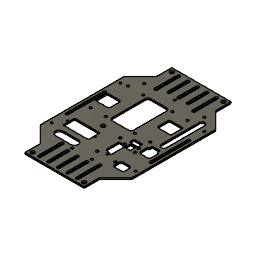
sheet for pi_lidar_optical_flow (Autodesk Fusion 360 design; units mm, degrees)
Autodesk Fusion 360 part; units mm, degrees
sketch "Sketch1" plane through (0, 0, 0) normal (0, 0, 1) x (1, 0, 0)
  line L0 (60, 55) -> (-60, 55)
  line L1 (-60, 55) -> (-60, -55)
  line L2 (-60, -55) -> (60, -55)
  line L3 (60, -55) -> (60, 55)
  line L4 (60, 55) -> (-60, -55) construction
  line L5 (-60, 55) -> (60, -55) construction
  line L6 (-60, 55) -> (-38.7868, 76.2132)
  line L7 (-60, 55) -> (-25, 55) construction
  line L8 (-38.7868, 76.2132) -> (-38.7868, 96.2132)
  line L9 (-38.7868, 96.2132) -> (38.7868, 96.2132)
  line L10 (38.7868, 96.2132) -> (38.7868, 76.2132)
  line L11 (38.7868, 76.2132) -> (60, 55)
  line L12 (70, 0) -> (110, 0)
  line L13 (-38.7868, -76.2132) -> (-38.7868, -96.2132)
  line L14 (-38.7868, -96.2132) -> (38.7868, -96.2132)
  line L15 (38.7868, -96.2132) -> (38.7868, -76.2132)
  line L16 (38.7868, -76.2132) -> (60, -55)
  line L17 (-60, -55) -> (-38.7868, -76.2132)
  dimension "d1" = 120
  dimension "d2" = 110
  dimension "d55" = 45
  dimension "d56" = 30
  dimension "d57" = 20
  dimension "d58" = 45
  constraint horizontal L0
  constraint perpendicular L0 L1
  constraint parallel L0 L2
  constraint parallel L1 L3
  constraint coincident L4 origin
  constraint coincident L5 origin
  constraint horizontal L7
  constraint perpendicular L0 L8
  constraint perpendicular L1 L9
  constraint perpendicular L9 L10
  constraint equal L6 L11
  constraint perpendicular L3 L12
  constraint symmetric L0.start L12 L2.end
  constraint symmetric L0.end L12 L1.end
  constraint symmetric L6.end L12 L13.start
  constraint symmetric L8.end L12 L13.end
  constraint symmetric L9.end L12 L14.end
  constraint symmetric L10.end L12 L15.end
  measures "d1" distance of L1.end L2.end
  measures "d2" distance of L0.end L1.end
  measures "d55" angle of L6 L7
  measures "d56" distance of L0.end L6.end
  measures "d57" distance of L6.end L8.end
  measures "d58" angle of L0 L11
extrude "Extrude1" add sketch "Sketch1" along normal blind 2
sketch "Sketch2" plane through (0, 0, 2) normal (0, 0, 1) x (-1, 0, 0)
  line L0 (-60, 55) -> (-60, -55)
  line L1 (60, -55) -> (60, 55)
  line L2 (45, 25) -> (12, 25)
  line L3 (12, 25) -> (12, 40)
  line L4 (12, 40) -> (45, 40)
  line L5 (45, 40) -> (45, 25)
  line L6 (-4.5, 15) -> (-50, 15)
  line L7 (-50, 15) -> (-50, 50)
  line L8 (-50, 50) -> (-4.5, 50)
  line L9 (-4.5, 50) -> (-4.5, 15)
  line L10 (50, -50) -> (-35, -50)
  line L11 (-35, -50) -> (-35, 6)
  line L12 (-35, 6) -> (50, 6)
  line L13 (50, 6) -> (50, -50)
  line L14 (55, 55) -> (-55, 55)
  line L15 (-55, 55) -> (-55, -55)
  line L16 (-55, -55) -> (55, -55)
  line L17 (55, -55) -> (55, 55)
  line L18 (60, 55) -> (38.7868, 76.2132)
  line L19 (38.7868, 76.2132) -> (38.7868, 96.2132)
  line L20 (38.7868, 96.2132) -> (-38.7868, 96.2132)
  line L21 (-38.7868, 96.2132) -> (-38.7868, 76.2132)
  line L22 (-38.7868, 76.2132) -> (-60, 55)
  line L23 (-60, -55) -> (-38.7868, -76.2132)
  line L24 (-38.7868, -76.2132) -> (-38.7868, -96.2132)
  line L25 (-38.7868, -96.2132) -> (38.7868, -96.2132)
  line L26 (38.7868, -96.2132) -> (38.7868, -76.2132)
  line L27 (38.7868, -76.2132) -> (60, -55)
  dimension "d5" = 33
  dimension "d6" = 15
  dimension "d7" = 45.5
  dimension "d8" = 35
  dimension "d9" = 85
  dimension "d10" = 56
  dimension "d13" = 5
  dimension "d14" = 5
  dimension "d15" = 5
  dimension "d16" = 5
  constraint horizontal L2
  constraint vertical L3
  constraint horizontal L4
  constraint vertical L5
  constraint horizontal L6
  constraint vertical L7
  constraint horizontal L8
  constraint vertical L9
  constraint horizontal L10
  constraint vertical L11
  constraint horizontal L12
  constraint vertical L13
  measures "d5" distance of L2.start L2.end
  measures "d6" distance of L2.start L4.end
  measures "d7" distance of L6.start L6.end
  measures "d8" distance of L6.start L8.end
  measures "d9" distance of L10.start L10.end
  measures "d10" distance of L10.start L12.end
  measures "d13" distance of L8 L14
  measures "d14" distance of L7 L15
  measures "d15" distance of L10 L16
  measures "d16" distance of L13 L17
sketch "px4 flow" plane through (0, 0, 2) normal (0, 0, 1) x (-1, 0, 0)
  line L0 (-4.5, 49) -> (-4.5, 15)
  line L1 (-50, 16) -> (-50, 49)
  line L2 (-5.5, 15) -> (-13, 15)
  line L3 (-13, 50) -> (-5.5, 50)
  line L4 (-4.5, 50) -> (-4.5, 16)
  line L5 (-34, 50) -> (-27, 50)
  line L6 (-27, 50) -> (-27, 16)
  line L7 (-29, 15) -> (-34, 15)
  line L8 (-38, 22) -> (-48, 22)
  line L9 (-50, 22) -> (-50, 43)
  line L10 (-45.6317, 43) -> (-36, 43)
  line L11 (-12.2169, 22.2704) -> (-18.4339, 23.652)
  line L12 (-20, 25.6043) -> (-20, 40.7534)
  line L13 (-18.7831, 41.7296) -> (-12.5661, 40.348)
  line L14 (-11, 38.3957) -> (-11, 23.2466)
  line L15 (-13, 15) -> (-13, 22.4444)
  line L16 (-13, 40.4444) -> (-13, 50)
  line L17 (-34, 45) -> (-34, 50)
  line L18 (-18, 15) -> (-19, 16)
  line L19 (-19, 16) -> (-27, 16)
  line L20 (-28, 16) -> (-29, 15)
  line L21 (-4.5, 15) -> (-18, 15)
  line L22 (-29, 15) -> (-36, 15)
  line L23 (-48, 22) -> (-50, 20)
  line L24 (-38, 22) -> (-36, 20)
  line L25 (-38, 22) -> (-35.1716, 22) construction
  line L26 (-36, 20) -> (-36, 15)
  line L27 (-50, 15) -> (-50, 50)
  arc A0 (-5.5, 15) -> (-4.5, 16) centre (-5.5, 16) ccw
  arc A1 (-4.5, 49) -> (-5.5, 50) centre (-5.5, 49) ccw
  arc A2 (-49, 50) -> (-50, 49) centre (-49, 49) ccw
  line L28 (-34, 45) -> (-36, 43)
  line L29 (-45.6317, 43) -> (-47.6317, 45)
  line L30 (-47.6317, 45) -> (-47.6317, 50)
  arc A3 (-12.2169, 22.2704) -> (-11, 23.2466) centre (-12, 23.2466) ccw
  arc A4 (-18.7831, 41.7296) -> (-20, 40.7534) centre (-19, 40.7534) ccw
  arc A5 (-20, 25.6043) -> (-18.4339, 23.652) centre (-18, 25.6043) ccw
  arc A6 (-11, 38.3957) -> (-12.5661, 40.348) centre (-13, 38.3957) ccw
  line L31 (-27, 16) -> (-28, 16)
  circle A7 centre (-7.1329, 17.151) radius 1.6654
  circle A8 centre (-31.1939, 17.1993) radius 1.6186
  circle A9 centre (-33.3, 24.1) radius 1.5796
  circle A10 centre (-31.1536, 47.5993) radius 1.6164
  circle A11 centre (-7.1536, 47.551) radius 1.638
  line L32 (-4.5, 15) -> (-50, 15)
  circle A12 centre (-17.1004, 43.6134) radius 1.713
  circle A13 centre (-17.2367, 21.5536) radius 1.75
  line L33 (-18, 15) -> (-18, 10.5)
  line L34 (-18.5, 10) -> (-28.5, 10)
  line L35 (-29, 10.5) -> (-29, 15)
  line L36 (-36, 15) -> (-36, 10.5)
  line L37 (-50, 10.5) -> (-50, 16)
  arc A14 (-18.5, 10) -> (-18, 10.5) centre (-18.5, 10.5) ccw
  arc A15 (-29, 10.5) -> (-28.5, 10) centre (-28.5, 10.5) ccw
  arc A16 (-36.5, 10) -> (-36, 10.5) centre (-36.5, 10.5) ccw
  arc A17 (-50, 10.5) -> (-49.5, 10) centre (-49.5, 10.5) ccw
  line L38 (-28, 25) -> (-20.7592, 25)
  line L39 (-20.7592, 25) -> (-20.7592, 17.3949)
  line L40 (-20.7592, 17.3949) -> (-28, 17.3949)
  line L41 (-28, 17.3949) -> (-28, 25)
  line L42 (-47.6317, 50) -> (-47.6317, 52)
  line L43 (-45.6317, 54) -> (-36, 54)
  line L44 (-34, 52) -> (-34, 50)
  line L45 (-48, 9.5) -> (-48, 6)
  line L46 (-48, 6) -> (-38, 6)
  line L47 (-38, 6) -> (-38, 9.5)
  line L48 (-36.5, 10) -> (-37.5, 10)
  line L49 (-48.5, 10) -> (-49.5, 10)
  arc A18 (-37.5, 10) -> (-38, 9.5) centre (-37.5, 9.5) ccw
  arc A19 (-48, 9.5) -> (-48.5, 10) centre (-48.5, 9.5) ccw
  arc A20 (-34, 52) -> (-36, 54) centre (-36, 52) ccw
  arc A21 (-45.6317, 54) -> (-47.6317, 52) centre (-45.6317, 52) ccw
  line L50 (-49, 50) -> (-47.6317, 50)
  line L51 (-34, 50) -> (-4.5, 50)
  point P0 (-34, 54)
  dimension "d17" = 45
  dimension "d18" = 45
  dimension "d19" = 1
  dimension "d20" = 90
  dimension "d21" = 1
  dimension "d22" = 2
  dimension "d23" = 30.4
  dimension "d24" = 24
  dimension "d25" = 30.4
  dimension "d26" = 3.2373
  dimension "d27" = 9.1
  dimension "d28" = 16.7
  dimension "d29" = 0.5
  dimension "d105" = 3.5
  dimension "d106" = 4
  dimension "d107" = 0.5
  dimension "d108" = 2
  constraint horizontal L2
  constraint vertical L15
  constraint horizontal L3
  constraint vertical L4
  constraint coincident L3.start L51
  constraint horizontal L5
  constraint vertical L6
  constraint horizontal L7
  constraint horizontal L8
  constraint vertical L9
  constraint horizontal L10
  constraint coincident L1 L9.end
  constraint parallel L12 L16
  constraint parallel L11 L13
  constraint parallel L14 L15
  constraint coincident L11 L15.end
  constraint coincident L13 L16.start
  constraint collinear L15 L16
  constraint perpendicular L6 L19
  constraint collinear L21 L22
  constraint coincident L1 L23.end
  constraint horizontal L25
  constraint perpendicular L22 L26
  constraint coincident L0.end L4
  constraint coincident L0.end L2
  constraint tangent L4 A0
  constraint tangent L2 A0
  constraint coincident L4.start L0
  constraint coincident L4.start L3
  constraint tangent L0 A1
  constraint tangent L3 A1
  constraint equal A0 A1
  constraint tangent A2 L50
  constraint tangent L1 A2
  constraint equal A0 A2
  constraint perpendicular L30 L50
  constraint tangent L11 A3
  constraint tangent L14 A3
  constraint tangent L12 A4
  constraint tangent L13 A4
  constraint equal A3 A4
  constraint tangent L11 A5
  constraint tangent L12 A5
  constraint tangent L13 A6
  constraint tangent L14 A6
  constraint equal A5 A6
  constraint perpendicular L21 L33
  constraint perpendicular L33 L34
  constraint vertical L35
  constraint perpendicular L32 L36
  constraint perpendicular L26 L48
  constraint tangent L33 A14
  constraint tangent L34 A14
  constraint tangent L34 A15
  constraint tangent L35 A15
  constraint equal A14 A15
  constraint tangent L36 A16
  constraint tangent A16 L48
  constraint equal A14 A16
  constraint tangent A17 L49
  constraint tangent L37 A17
  constraint equal A14 A17
  constraint horizontal L38
  constraint vertical L39
  constraint horizontal L40
  constraint vertical L41
  constraint parallel L42 L44
  constraint vertical L45
  constraint horizontal L46
  constraint vertical L47
  constraint collinear L48 L49
  constraint tangent L47 A18
  constraint tangent L48 A18
  constraint tangent L45 A19
  constraint tangent L49 A19
  constraint equal A18 A19
  constraint coincident P0 L43
  constraint coincident P0 L44
  constraint tangent L43 A20
  constraint tangent L44 A20
  constraint tangent L42 A21
  constraint tangent L43 A21
  constraint equal A20 A21
  constraint collinear L50 L51
  measures "d17" angle of L24 L25
  measures "d18" angle of L23 L27
  measures "d19" radius of A0
  measures "d20" angle of L28 L29
  measures "d21" radius of A3
  measures "d22" radius of A5
  measures "d23" vertical distance of A7.centre A11.centre
  measures "d24" horizontal distance of A10.centre A11.centre
  measures "d25" vertical distance of A8.centre A10.centre
  measures "d26" diameter of A8
  measures "d27" distance of A9.centre L32
  measures "d28" distance of L27 A9.centre
  measures "d29" radius of A14
  measures "d105" diameter of A13
  measures "d106" distance of L5.start P0
  measures "d107" radius of A18
  measures "d108" radius of A20
sketch "Raspberry Pi" plane through (0, 0, 2) normal (0, 0, 1) x (-1, 0, 0)
  line L0 (-35, 6) -> (50, 6)
  line L1 (50, 6) -> (50, -50)
  line L2 (-35, -50) -> (-35, 6)
  line L3 (50, -50) -> (-35, -50)
  line L4 (50, 6) -> (50, -50)
  line L5 (50, -25) -> (36, -25)
  line L6 (34, -23) -> (34, -11)
  line L7 (36, -9) -> (50, -9)
  line L8 (50, -9) -> (50, -25)
  line L9 (-35, 6) -> (50, 6)
  line L10 (-35, -35) -> (-21, -35)
  line L11 (-19, -33) -> (-19, -21)
  line L12 (-21, -19) -> (-35, -19)
  line L13 (-35, -19) -> (-35, -35)
  line L14 (-35, -50) -> (-35, 6)
  line L15 (17.5, -47) -> (-3.5, -47)
  line L16 (-7, -43.5) -> (-7, -0.5)
  line L17 (-3.5, 3) -> (17.5, 3)
  line L18 (21, -0.5) -> (21, -43.5)
  arc A0 (17.5, -47) -> (21, -43.5) centre (17.5, -43.5) ccw
  arc A1 (-7, -43.5) -> (-3.5, -47) centre (-3.5, -43.5) ccw
  arc A2 (21, -0.5) -> (17.5, 3) centre (17.5, -0.5) ccw
  arc A3 (-3.5, 3) -> (-7, -0.5) centre (-3.5, -0.5) ccw
  arc A4 (34, -23) -> (36, -25) centre (36, -23) ccw
  arc A5 (36, -9) -> (34, -11) centre (36, -11) ccw
  arc A6 (-21, -35) -> (-19, -33) centre (-21, -33) ccw
  arc A7 (-19, -21) -> (-21, -19) centre (-21, -21) ccw
  line L19 (50, -25) -> (52, -25)
  line L20 (52, -25) -> (52, -9)
  line L21 (52, -9) -> (50, -9)
  line L22 (50, -9) -> (50, -25)
  line L23 (-35, -35) -> (-37, -35)
  line L24 (-37, -35) -> (-37, -19)
  line L25 (-37, -19) -> (-35, -19)
  line L26 (-35, -19) -> (-35, -35)
  point P0 (46.5, -46.5)
  point P1 (46.5, 2.5)
  point P2 (-11.5, -46.5)
  point P3 (-11.5, 2.5)
  point P4 (-31.5, -46.5)
  point P5 (-31.5, 2.5)
  point P6 (26.5, -46.5)
  point P7 (26.5, 2.5)
  point P8 (34, -25)
  dimension "d30" = 3.5
  dimension "d31" = 3.5
  dimension "d32" = 3.5
  dimension "d33" = 3.5
  dimension "d34" = 3.5
  dimension "d35" = 3.5
  dimension "d36" = 3.5
  dimension "d37" = 3.5
  dimension "d38" = 58
  dimension "d39" = 49
  dimension "d40" = 16
  dimension "d41" = 25
  dimension "d42" = 15
  dimension "d43" = 15
  dimension "d44" = 25
  dimension "d45" = 16
  dimension "d46" = 3.5
  dimension "d47" = 2
  constraint horizontal L5
  constraint vertical L6
  constraint horizontal L7
  constraint vertical L8
  constraint coincident L1 L5.start
  constraint horizontal L10
  constraint vertical L11
  constraint horizontal L12
  constraint vertical L13
  constraint coincident L2 L10.start
  constraint horizontal L15
  constraint vertical L16
  constraint horizontal L17
  constraint vertical L18
  constraint tangent L15 A0
  constraint tangent L18 A0
  constraint tangent L15 A1
  constraint tangent L16 A1
  constraint equal A0 A1
  constraint tangent L18 A2
  constraint tangent L17 A2
  constraint equal A0 A2
  constraint tangent L16 A3
  constraint tangent L17 A3
  constraint equal A0 A3
  constraint coincident P8 L5
  constraint coincident P8 L6
  constraint tangent L5 A4
  constraint tangent L6 A4
  constraint tangent L6 A5
  constraint tangent L7 A5
  constraint equal A4 A5
  constraint tangent L10 A6
  constraint tangent L11 A6
  constraint equal A4 A6
  constraint tangent L11 A7
  constraint tangent L12 A7
  constraint equal A4 A7
  constraint horizontal L19
  constraint vertical L20
  constraint horizontal L21
  constraint vertical L22
  constraint horizontal L23
  constraint vertical L24
  constraint horizontal L25
  constraint vertical L26
  measures "d30" distance of L1 P0
  measures "d31" distance of L3 P0
  measures "d32" distance of P1 L4
  measures "d33" distance of L0 P1
  measures "d34" distance of L2 P4
  measures "d35" distance of L2 P5
  measures "d36" distance of L3 P4
  measures "d37" distance of L0 P5
  measures "d38" distance of P0 P2
  measures "d39" distance of P2 P3
  measures "d40" distance of L5.start P8
  measures "d41" distance of L3 L5
  measures "d42" distance of L7 L9
  measures "d43" distance of L3 L10
  measures "d44" distance of L9 L12
  measures "d45" distance of L11 L14
  measures "d46" radius of A0
  measures "d47" radius of A4
sketch "tf mini lidar" plane through (0, 0, 2) normal (0, 0, 1) x (-1, 0, 0)
  line L0 (12.5, 40) -> (44.5, 40)
  line L1 (45, 39.5) -> (45, 25.5)
  line L2 (12, 25.5) -> (12, 39.5)
  line L3 (44.5, 25) -> (12.5, 25)
  circle A0 centre (46.5, 32.5) radius 1.175
  circle A1 centre (10.5, 32.5) radius 1.175
  line L4 (12, 25) -> (12, 40)
  arc A2 (44.5, 25) -> (45, 25.5) centre (44.5, 25.5) ccw
  arc A3 (45, 39.5) -> (44.5, 40) centre (44.5, 39.5) ccw
  arc A4 (12.5, 40) -> (12, 39.5) centre (12.5, 39.5) ccw
  arc A5 (12, 25.5) -> (12.5, 25) centre (12.5, 25.5) ccw
  dimension "d48" = 36
  dimension "d49" = 1.5
  dimension "d50" = 2.35
  dimension "d51" = 2.35
  dimension "d52" = 7.5
  dimension "d53" = 7.5
  dimension "d54" = 0.5
  constraint tangent L1 A2
  constraint tangent L3 A2
  constraint tangent L0 A3
  constraint tangent L1 A3
  constraint equal A2 A3
  constraint tangent L0 A4
  constraint tangent L2 A4
  constraint equal A2 A4
  constraint tangent L2 A5
  constraint tangent L3 A5
  constraint equal A2 A5
  measures "d48" horizontal distance of A0.centre A1.centre
  measures "d49" distance of A1.centre L4
  measures "d50" diameter of A1
  measures "d51" diameter of A0
  measures "d52" distance of L3 A0.centre
  measures "d53" distance of L3 A1.centre
  measures "d54" radius of A2
sketch "holes" plane through (0, 0, 2) normal (0, 0, 1) x (-1, 0, 0)
  line L0 (60, -55) -> (60, 55)
  line L1 (60, 55) -> (38.7868, 76.2132)
  line L2 (38.7868, 76.2132) -> (38.7868, 96.2132)
  line L3 (38.7868, 96.2132) -> (-38.7868, 96.2132)
  line L4 (-38.7868, 96.2132) -> (-38.7868, 76.2132)
  line L5 (-38.7868, 76.2132) -> (-60, 55)
  line L6 (-60, 55) -> (-60, -55)
  line L7 (-60, -55) -> (-38.7868, -76.2132)
  line L8 (-38.7868, -76.2132) -> (-38.7868, -96.2132)
  line L9 (-38.7868, -96.2132) -> (38.7868, -96.2132)
  line L10 (38.7868, -96.2132) -> (38.7868, -76.2132)
  line L11 (38.7868, -76.2132) -> (60, -55)
  line L12 (56.5, -25) -> (56.5, 25)
  arc A0 (56.5, 25) -> (53.5, 25) centre (55, 25) ccw
  line L13 (53.5, 25) -> (53.5, -25)
  arc A1 (53.5, -25) -> (56.5, -25) centre (55, -25) ccw
  line L14 (55, -25) -> (55, 25) construction
  line L15 (-53.5, -25) -> (-53.5, 25)
  arc A2 (-53.5, 25) -> (-56.5, 25) centre (-55, 25) ccw
  line L16 (-56.5, 25) -> (-56.5, -25)
  arc A3 (-56.5, -25) -> (-53.5, -25) centre (-55, -25) ccw
  line L17 (-55, -25) -> (-55, 25) construction
  line L18 (38, 57) -> (18, 57)
  arc A4 (18, 57) -> (18, 47) centre (18, 52) ccw
  line L19 (18, 47) -> (38, 47)
  arc A5 (38, 47) -> (38, 57) centre (38, 52) ccw
  line L20 (38, 52) -> (18, 52) construction
  line L21 (-41.5, -52) -> (-41.5, -2)
  arc A6 (-41.5, -2) -> (-48.5, -2) centre (-45, -2) ccw
  line L22 (-48.5, -2) -> (-48.5, -52)
  arc A7 (-48.5, -52) -> (-41.5, -52) centre (-45, -52) ccw
  line L23 (-45, -52) -> (-45, -2) construction
  point P0 (55, -45)
  point P1 (-55, -45)
  point P2 (55, 45)
  point P3 (-55, 45)
  point P4 (12.9288, 60.3583)
  point P5 (-12.9288, 60.2132)
  point P6 (38.7872, -60)
  point P7 (-38.7868, -61.0687)
  point P8 (0.0002, -61.0687)
  point P9 (33.7868, 91.2132)
  point P10 (-33.7868, 91.2132)
  point P11 (33.7868, -91.2132)
  point P12 (-33.7868, -91.2132)
  point P13 (17.6878, 14.8368)
  dimension "d60" = 3
  dimension "d61" = 3
  dimension "d62" = 110
  dimension "d63" = 5
  dimension "d64" = 5
  dimension "d65" = 50
  dimension "d66" = 50
  dimension "d67" = 30
  dimension "d68" = 5
  dimension "d69" = 5
  dimension "d70" = 5
  dimension "d71" = 5
  dimension "d72" = 10
  dimension "d73" = 10
  dimension "d74" = 10
  dimension "d75" = 10
  dimension "d76" = 25.858
  dimension "d77" = 25.858
  dimension "d78" = 25.858
  dimension "d79" = 16
  dimension "d80" = 77.574
  dimension "d81" = 38.787
  dimension "d82" = 38.787
  dimension "d83" = 50
  dimension "d84" = 7
  dimension "d85" = 5
  dimension "d86" = 5
  dimension "d87" = 5
  dimension "d88" = 5
  dimension "d89" = 5
  dimension "d90" = 5
  dimension "d91" = 5
  dimension "d92" = 5
  dimension "d109" = 3
  constraint tangent L12 A0
  constraint tangent A0 L13
  constraint parallel L12 L13
  constraint tangent L13 A1
  constraint tangent L12 A1
  constraint parallel L0 L14
  constraint tangent L15 A2
  constraint tangent A2 L16
  constraint parallel L15 L16
  constraint tangent L16 A3
  constraint tangent L15 A3
  constraint parallel L6 L17
  constraint tangent L18 A4
  constraint tangent A4 L19
  constraint parallel L18 L19
  constraint tangent L19 A5
  constraint tangent L18 A5
  constraint perpendicular L0 L20
  constraint tangent L21 A6
  constraint tangent A6 L22
  constraint parallel L21 L22
  constraint tangent L22 A7
  constraint tangent L21 A7
  constraint vertical L23
  measures "d60" diameter of A0
  measures "d61" diameter of A2
  measures "d62" distance of A1.centre A3.centre
  measures "d63" distance of L0 A1.centre
  measures "d64" distance of L6 A3.centre
  measures "d65" distance of A3.centre A2.centre
  measures "d66" distance of A1.centre A0.centre
  measures "d67" vertical distance of L6.end A3.centre
  measures "d68" distance of L0 P0
  measures "d69" distance of L0 P2
  measures "d70" distance of L6 P3
  measures "d71" distance of L6 P1
  measures "d72" vertical distance of L6.end P1
  measures "d73" vertical distance of L0.start P0
  measures "d74" vertical distance of L0.end P2
  measures "d75" vertical distance of L5.end P3
  measures "d76" distance of L2 P4
  measures "d77" distance of L4 P5
  measures "d78" distance of P4 P5
  measures "d79" vertical distance of L4.end P5
  measures "d80" distance of L8 P6
  measures "d81" horizontal distance of P6 P8
  measures "d82" distance of P7 P8
  measures "d83" distance of A7.centre A6.centre
  measures "d84" diameter of A6
  measures "d85" distance of L10 P11
  measures "d86" distance of L9 P11
  measures "d87" vertical distance of L8.end P12
  measures "d88" horizontal distance of L8.end P12
  measures "d89" distance of L2 P9
  measures "d90" distance of L4 P10
  measures "d91" vertical distance of L2.end P9
  measures "d92" vertical distance of L3.end P10
  measures "d109" vertical distance of L6.end A7.centre
hole "Hole1" at (-38.7872, 60, 2) at (-0.0002, 61.0687, 2) at (38.7868, 61.0687, 2) at (-55, 45, 2) at (-55, -45, 2) at (-12.9288, -60.3583, 2) at (12.9288, -60.2132, 2) at (55, -45, 2) at (55, 45, 2) at (-46.5, 46.5, 2) at (-46.5, -2.5, 2) at (-26.5, 46.5, 2) at (-26.5, -2.5, 2) at (11.5, 46.5, 2) at (31.5, 46.5, 2) at (11.5, -2.5, 2) at (31.5, -2.5, 2) direction (0, 0, -1) diameter 3 depth 50 tip angle 180
extrude "Extrude2" cut sketch "holes" sketch "tf mini lidar" against normal blind 20 contours L12 A0 L13 A1 | L15 A2 L16 A3 | L18 A4 L19 A5 | L21 A6 L22 A7 of sketch 2
hole "Hole2" at (-33.7868, 91.2132, 2) at (33.7868, 91.2132, 2) at (-33.7868, -91.2132, 2) at (33.7868, -91.2132, 2) at (-17.6878, -14.8368, 2) direction (0, 0, -1) diameter 5 depth 50 tip angle 180
extrude "Extrude3" cut sketch "Raspberry Pi" against normal blind 15 contours L2 L10 L11 L12 L13 L14 A6 A7 L26 | L2 L13 L14 L23 L24 L25 L26 | L1 L4 L8 L19 L20 L21 L22 | L1 L4 L5 L6 L7 L8 A4 A5 L22 | L15 L16 L17 L18 A0 A1 A2 A3
extrude "Extrude4" cut sketch "px4 flow" against normal blind 7 contours L11 L12 L13 L14 A3 A4 A5 A6 | L18 L19 L20 L31 L32 | L32 L33 L34 L35 A14 A15 | L10 L17 L28 L29 L30 L42 L43 L44 A20 A21 | L6 L38 L39 L40 | L6 L38 L40 L41 | L1 L8 L23 L24 L26 L27 L32 L37 | L32 L36 L37 A16 A17 L45 L46 L47 L48 L49 A18 A19 | A7 | A8 | A9 | A10 | A11 | A12 | A13
sketch "Sketch7" plane through (0, 0, 2) normal (0, 0, 1) x (-1, 0, 0)
  circle A0 centre (-31.1536, 47.5993) radius 1.6164
  circle A1 centre (-17.2367, 21.5536) radius 1.75
  line L0 (-27, 16) -> (-19, 16)
  line L1 (-19, 16) -> (-18, 15)
  line L2 (-18, 15) -> (-18, 10.5)
  arc A2 (-18.5, 10) -> (-18, 10.5) centre (-18.5, 10.5) ccw
  line L3 (-18.5, 10) -> (-28.5, 10)
  arc A3 (-29, 10.5) -> (-28.5, 10) centre (-28.5, 10.5) ccw
  line L4 (-29, 10.5) -> (-29, 15)
  line L5 (-29, 15) -> (-28, 16)
  line L6 (-28, 16) -> (-27, 16)
  circle A4 centre (-17.1004, 43.6134) radius 1.713
  circle A5 centre (-33.3, 24.1) radius 1.5796
  line L7 (-45.6317, 43) -> (-47.6317, 45)
  line L8 (-47.6317, 45) -> (-47.6317, 52)
  arc A6 (-45.6317, 54) -> (-47.6317, 52) centre (-45.6317, 52) ccw
  line L9 (-45.6317, 54) -> (-36, 54)
  arc A7 (-34, 52) -> (-36, 54) centre (-36, 52) ccw
  line L10 (-34, 52) -> (-34, 50)
  line L11 (-34, 50) -> (-34, 45)
  line L12 (-34, 45) -> (-36, 43)
  line L13 (-36, 43) -> (-45.6317, 43)
  line L14 (-50, 20) -> (-48, 22)
  line L15 (-48, 22) -> (-38, 22)
  line L16 (-38, 22) -> (-36, 20)
  line L17 (-36, 20) -> (-36, 10.5)
  arc A8 (-36.5, 10) -> (-36, 10.5) centre (-36.5, 10.5) ccw
  line L18 (-36.5, 10) -> (-37.5, 10)
  arc A9 (-37.5, 10) -> (-38, 9.5) centre (-37.5, 9.5) ccw
  line L19 (-38, 9.5) -> (-38, 6)
  line L20 (-38, 6) -> (-48, 6)
  line L21 (-48, 6) -> (-48, 9.5)
  arc A10 (-48, 9.5) -> (-48.5, 10) centre (-48.5, 9.5) ccw
  line L22 (-48.5, 10) -> (-49.5, 10)
  arc A11 (-50, 10.5) -> (-49.5, 10) centre (-49.5, 10.5) ccw
  line L23 (-50, 10.5) -> (-50, 16)
  line L24 (-50, 16) -> (-50, 20)
  line L25 (-11, 38.3957) -> (-11, 23.2466)
  arc A12 (-12.2169, 22.2704) -> (-11, 23.2466) centre (-12, 23.2466) ccw
  line L26 (-12.2169, 22.2704) -> (-18.4339, 23.652)
  arc A13 (-20, 25.6043) -> (-18.4339, 23.652) centre (-18, 25.6043) ccw
  line L27 (-20, 25.6043) -> (-20, 40.7534)
  arc A14 (-18.7831, 41.7296) -> (-20, 40.7534) centre (-19, 40.7534) ccw
  line L28 (-18.7831, 41.7296) -> (-12.5661, 40.348)
  arc A15 (-11, 38.3957) -> (-12.5661, 40.348) centre (-13, 38.3957) ccw
  circle A16 centre (-7.1329, 17.151) radius 1.6654
  circle A17 centre (-7.1536, 47.551) radius 1.638
  circle A18 centre (-31.1939, 17.1993) radius 1.6186
  line L29 (-20.7592, 25) -> (-20.7592, 17.3949)
  line L30 (-20.7592, 17.3949) -> (-28, 17.3949)
  line L31 (-28, 17.3949) -> (-28, 25)
  line L32 (-28, 25) -> (-20.7592, 25)
  line L33 (-3.5, 3) -> (17.5, 3)
  arc A19 (21, -0.5) -> (17.5, 3) centre (17.5, -0.5) ccw
  line L34 (21, -0.5) -> (21, -43.5)
  arc A20 (17.5, -47) -> (21, -43.5) centre (17.5, -43.5) ccw
  line L35 (17.5, -47) -> (-3.5, -47)
  arc A21 (-7, -43.5) -> (-3.5, -47) centre (-3.5, -43.5) ccw
  line L36 (-7, -43.5) -> (-7, -0.5)
  arc A22 (-3.5, 3) -> (-7, -0.5) centre (-3.5, -0.5) ccw
  line L37 (52, -9) -> (52, -25)
  line L38 (52, -25) -> (36, -25)
  arc A23 (34, -23) -> (36, -25) centre (36, -23) ccw
  line L39 (34, -23) -> (34, -11)
  arc A24 (36, -9) -> (34, -11) centre (36, -11) ccw
  line L40 (36, -9) -> (52, -9)
  arc A25 (-21, -35) -> (-19, -33) centre (-21, -33) ccw
  line L41 (-21, -35) -> (-37, -35)
  line L42 (-37, -35) -> (-37, -19)
  line L43 (-37, -19) -> (-21, -19)
  arc A26 (-19, -21) -> (-21, -19) centre (-21, -21) ccw
  line L44 (-19, -21) -> (-19, -33)
  circle A27 centre (33.7868, 91.2132) radius 2.5
  circle A28 centre (33.7868, -91.2132) radius 2.5
  circle A29 centre (-33.7868, -91.2132) radius 2.5
  circle A30 centre (-33.7868, 91.2132) radius 2.5
  line L45 (12, 25.5) -> (12, 39.5)
  arc A31 (12.5, 40) -> (12, 39.5) centre (12.5, 39.5) ccw
  line L46 (12.5, 40) -> (44.5, 40)
  arc A32 (45, 39.5) -> (44.5, 40) centre (44.5, 39.5) ccw
  line L47 (45, 39.5) -> (45, 25.5)
  arc A33 (44.5, 25) -> (45, 25.5) centre (44.5, 25.5) ccw
  line L48 (44.5, 25) -> (12.5, 25)
  arc A34 (12, 25.5) -> (12.5, 25) centre (12.5, 25.5) ccw
  line L49 (-53.5, 25) -> (-53.5, -25)
  arc A35 (-56.5, -25) -> (-53.5, -25) centre (-55, -25) ccw
  line L50 (-56.5, -25) -> (-56.5, 25)
  arc A36 (-53.5, 25) -> (-56.5, 25) centre (-55, 25) ccw
  line L51 (56.5, 25) -> (56.5, -25)
  arc A37 (53.5, -25) -> (56.5, -25) centre (55, -25) ccw
  line L52 (53.5, -25) -> (53.5, 25)
  arc A38 (56.5, 25) -> (53.5, 25) centre (55, 25) ccw
  line L53 (-41.5, -2) -> (-41.5, -52)
  arc A39 (-48.5, -52) -> (-41.5, -52) centre (-45, -52) ccw
  line L54 (-48.5, -52) -> (-48.5, -2)
  arc A40 (-41.5, -2) -> (-48.5, -2) centre (-45, -2) ccw
  line L55 (18, 57) -> (38, 57)
  arc A41 (38, 47) -> (38, 57) centre (38, 52) ccw
  line L56 (38, 47) -> (18, 47)
  arc A42 (18, 57) -> (18, 47) centre (18, 52) ccw
  circle A43 centre (46.5, 32.5) radius 1.175
  circle A44 centre (10.5, 32.5) radius 1.175
  circle A45 centre (-11.5, 2.5) radius 1.5
  circle A46 centre (-11.5, -46.5) radius 1.5
  circle A47 centre (26.5, -46.5) radius 1.5
  circle A48 centre (46.5, -46.5) radius 1.5
  circle A49 centre (-55, 45) radius 1.5
  circle A50 centre (12.9288, 60.3583) radius 1.5
  circle A51 centre (55, -45) radius 1.5
  circle A52 centre (0.0002, -61.0687) radius 1.5
  circle A53 centre (38.7872, -60) radius 1.5
  circle A54 centre (-38.7868, -61.0687) radius 1.5
  circle A55 centre (55, 45) radius 1.5
  circle A56 centre (-12.9288, 60.2132) radius 1.5
  circle A57 centre (-55, -45) radius 1.5
  circle A58 centre (46.5, 2.5) radius 1.5
  circle A59 centre (26.5, 2.5) radius 1.5
  circle A60 centre (-31.5, -46.5) radius 1.5
  circle A61 centre (-31.5, 2.5) radius 1.5
  line L57 (60, -55) -> (60, 55)
  line L58 (60, 55) -> (38.7868, 76.2132)
  line L59 (38.7868, 76.2132) -> (38.7868, 96.2132)
  line L60 (38.7868, 96.2132) -> (-38.7868, 96.2132)
  line L61 (-38.7868, 96.2132) -> (-38.7868, 76.2132)
  line L62 (-38.7868, 76.2132) -> (-60, 55)
  line L63 (-60, 55) -> (-60, -55)
  line L64 (-60, -55) -> (-38.7868, -76.2132)
  line L65 (-38.7868, -76.2132) -> (-38.7868, -96.2132)
  line L66 (-38.7868, -96.2132) -> (38.7868, -96.2132)
  line L67 (38.7868, -96.2132) -> (38.7868, -76.2132)
  line L68 (38.7868, -76.2132) -> (60, -55)
  line L69 (33.7868, -91.2132) -> (-33.7868, -91.2132)
  line L70 (26.5368, -91.2132) -> (26.5368, -61.2132)
  arc A62 (26.5368, -61.2132) -> (23.0368, -61.2132) centre (24.7868, -61.2132) ccw
  line L71 (23.0368, -61.2132) -> (23.0368, -91.2132)
  arc A63 (23.0368, -91.2132) -> (26.5368, -91.2132) centre (24.7868, -91.2132) ccw
  line L72 (24.7868, -91.2132) -> (24.7868, -61.2132) construction
  line L73 (24.7868, -91.2132) -> (53.9321, -91.2132) construction
  line L74 (-23.0368, -91.2132) -> (-23.0368, -61.2132)
  arc A64 (-23.0368, -61.2132) -> (-26.5368, -61.2132) centre (-24.7868, -61.2132) ccw
  line L75 (-26.5368, -61.2132) -> (-26.5368, -91.2132)
  arc A65 (-26.5368, -91.2132) -> (-23.0368, -91.2132) centre (-24.7868, -91.2132) ccw
  line L76 (-24.7868, -91.2132) -> (-24.7868, -61.2132) construction
  line L77 (-24.7868, -91.2132) -> (3.712, -91.2132) construction
  line L78 (14.3565, -91.2132) -> (14.3565, -66.2132)
  arc A66 (14.3565, -66.2132) -> (10.8565, -66.2132) centre (12.6065, -66.2132) ccw
  line L79 (10.8565, -66.2132) -> (10.8565, -91.2132)
  arc A67 (10.8565, -91.2132) -> (14.3565, -91.2132) centre (12.6065, -91.2132) ccw
  line L80 (12.6065, -91.2132) -> (12.6065, -66.2132) construction
  line L81 (-10.6433, -91.2132) -> (-10.6433, -66.2132)
  arc A68 (-10.6433, -66.2132) -> (-14.1433, -66.2132) centre (-12.3933, -66.2132) ccw
  line L82 (-14.1433, -66.2132) -> (-14.1433, -91.2132)
  arc A69 (-14.1433, -91.2132) -> (-10.6433, -91.2132) centre (-12.3933, -91.2132) ccw
  line L83 (-12.3933, -91.2132) -> (-12.3933, -66.2132) construction
  line L84 (-12.3933, -91.2132) -> (12.6067, -91.2132) construction
  line L85 (1.75, -91.2132) -> (1.75, -66.2132)
  arc A70 (1.75, -66.2132) -> (-1.75, -66.2132) centre (0, -66.2132) ccw
  line L86 (-1.75, -66.2132) -> (-1.75, -91.2132)
  arc A71 (-1.75, -91.2132) -> (1.75, -91.2132) centre (0, -91.2132) ccw
  line L87 (0, -91.2132) -> (0, -66.2132) construction
  line L88 (0, -91.2132) -> (25, -91.2132) construction
  line L89 (-75, 0) -> (-110, 0)
  line L90 (23.0368, 61.2132) -> (23.0368, 91.2132)
  arc A72 (26.5368, 91.2132) -> (23.0368, 91.2132) centre (24.7868, 91.2132) ccw
  arc A73 (23.0368, 61.2132) -> (26.5368, 61.2132) centre (24.7868, 61.2132) ccw
  line L91 (26.5368, 91.2132) -> (26.5368, 61.2132)
  line L92 (10.8565, 66.2132) -> (10.8565, 91.2132)
  arc A74 (14.3565, 91.2132) -> (10.8565, 91.2132) centre (12.6065, 91.2132) ccw
  arc A75 (10.8565, 66.2132) -> (14.3565, 66.2132) centre (12.6065, 66.2132) ccw
  line L93 (14.3565, 91.2132) -> (14.3565, 66.2132)
  line L94 (-1.75, 66.2132) -> (-1.75, 91.2132)
  arc A76 (1.75, 91.2132) -> (-1.75, 91.2132) centre (0, 91.2132) ccw
  arc A77 (-1.75, 66.2132) -> (1.75, 66.2132) centre (0, 66.2132) ccw
  line L95 (1.75, 91.2132) -> (1.75, 66.2132)
  line L96 (-14.1433, 66.2132) -> (-14.1433, 91.2132)
  arc A78 (-10.6433, 91.2132) -> (-14.1433, 91.2132) centre (-12.3933, 91.2132) ccw
  arc A79 (-14.1433, 66.2132) -> (-10.6433, 66.2132) centre (-12.3933, 66.2132) ccw
  line L97 (-10.6433, 91.2132) -> (-10.6433, 66.2132)
  line L98 (-26.5368, 61.2132) -> (-26.5368, 91.2132)
  arc A80 (-23.0368, 91.2132) -> (-26.5368, 91.2132) centre (-24.7868, 91.2132) ccw
  arc A81 (-26.5368, 61.2132) -> (-23.0368, 61.2132) centre (-24.7868, 61.2132) ccw
  line L99 (-23.0368, 91.2132) -> (-23.0368, 61.2132)
  circle A82 centre (17.6878, 14.8368) radius 2.5
  dimension "d110" = 30
  dimension "d111" = 90
  dimension "d112" = 3.5
  dimension "d113" = 30
  dimension "d114" = 90
  dimension "d115" = 3.5
  dimension "d116" = 25
  dimension "d117" = 3.5
  dimension "d118" = 25
  dimension "d119" = 90
  dimension "d120" = 3.5
  dimension "d121" = 25
  dimension "d122" = 90
  dimension "d123" = 3.5
  dimension "d124" = 9
  dimension "d125" = 9
  dimension "d126" = 12.3935
  dimension "d127" = 12.3935
  constraint coincident A28.centre L69.start
  constraint coincident A29.centre L69.end
  constraint tangent L70 A62
  constraint tangent A62 L71
  constraint parallel L70 L71
  constraint tangent L71 A63
  constraint tangent L70 A63
  constraint coincident L69 A63.centre
  constraint tangent L74 A64
  constraint tangent A64 L75
  constraint parallel L74 L75
  constraint tangent L75 A65
  constraint tangent L74 A65
  constraint coincident L69 A65.centre
  constraint tangent L78 A66
  constraint tangent A66 L79
  constraint parallel L78 L79
  constraint tangent L79 A67
  constraint tangent L78 A67
  constraint perpendicular L69 L80
  constraint coincident L69 A67.centre
  constraint tangent L81 A68
  constraint tangent A68 L82
  constraint parallel L81 L82
  constraint tangent L82 A69
  constraint tangent L81 A69
  constraint coincident L77 A69.centre
  constraint tangent L85 A70
  constraint tangent A70 L86
  constraint parallel L85 L86
  constraint tangent L86 A71
  constraint tangent L85 A71
  constraint midpoint L69 A71.centre
  constraint horizontal L89
  constraint symmetric L70.start L89 A72.start
  constraint symmetric L70.end L89 A73.end
  constraint symmetric A62.end L89 L90.start
  constraint symmetric L71.end L89 L90.end
  constraint symmetric A62 L89 A73
  constraint symmetric A63 L89 A72
  constraint symmetric L74.start L89 A80.start
  constraint symmetric L74.end L89 A81.end
  constraint symmetric A64.end L89 L98.start
  constraint symmetric L75.end L89 L98.end
  constraint symmetric A64 L89 A81
  constraint symmetric A65 L89 A80
  constraint symmetric L78.start L89 A74.start
  constraint symmetric L78.end L89 A75.end
  constraint symmetric A66.end L89 L92.start
  constraint symmetric L79.end L89 L92.end
  constraint symmetric A66 L89 A75
  constraint symmetric A67 L89 A74
  constraint symmetric L81.start L89 A78.start
  constraint symmetric L81.end L89 A79.end
  constraint symmetric A68.end L89 L96.start
  constraint symmetric L82.end L89 L96.end
  constraint symmetric A68 L89 A79
  constraint symmetric A69 L89 A78
  constraint symmetric L85.start L89 A76.start
  constraint symmetric L85.end L89 A77.end
  constraint symmetric A70.end L89 L94.start
  constraint symmetric L86.end L89 L94.end
  constraint symmetric A70 L89 A77
  constraint symmetric A71 L89 A76
  measures "d110" distance of A63.centre A62.centre
  measures "d111" angle of L72 L73
  measures "d112" diameter of A62
  measures "d113" distance of A65.centre A64.centre
  measures "d114" angle of L76 L77
  measures "d115" diameter of A64
  measures "d116" distance of A67.centre A66.centre
  measures "d117" diameter of A66
  measures "d118" distance of A69.centre A68.centre
  measures "d119" angle of L83 L84
  measures "d120" diameter of A68
  measures "d121" distance of A71.centre A70.centre
  measures "d122" angle of L87 L88
  measures "d123" diameter of A70
  measures "d124" distance of A28.centre A63.centre
  measures "d125" distance of A29.centre A65.centre
  measures "d126" distance of A67.centre L88.end
  measures "d127" distance of A65.centre A69.centre
extrude "Extrude5" cut sketch "Sketch7" against normal blind 60 contours L69 A63 | L69 L70 A62 L71 | L69 A67 | L69 L78 A66 L79 | L69 A71 | L69 L85 A70 L86 | L69 A69 | L69 L81 A68 L82 | L69 A65 | L69 L74 A64 L75 | L90 A72 A73 L91 | L92 A74 A75 L93 | L94 A76 A77 L95 | L96 A78 A79 L97 | L98 A80 A81 L99
equation "d81 = ( 77.574 / 2 ) * 1 mm"
equation "d126 = ( 49.574 / 4 ) * 1 mm"
equation "d127 = ( 49.574 / 4 ) * 1 mm"
